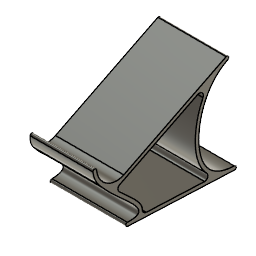
robot stand (Autodesk Fusion 360 design; units mm, degrees)
part number: 2026-07-23-08-51-04-627
Autodesk Fusion 360 part; units mm, degrees
sketch "Sketch1" plane through (0, 0, 0) normal (1, 0, 0) x (0, 1, 0)
  line L0 (-30, 0) -> (30, 30)
  arc A0 (-44.4721, 8.9443) -> (-30, 0) centre (-34.4721, 8.9443) ccw
  line L1 (30, -25) -> (-30, -25)
  arc A1 (-46.4721, 8.9443) -> (-43.4408, 0.9716) centre (-34.4721, 8.9443) ccw
  spline S0 degree 5 poles (-41.8278, -0.8884) (-40.6864, -2.2379) (-37.8165, -5.2912) (-32.5736, -10.0274) (-25.3421, -16.0716) (-21.7331, -20.6178) (-23.6292, -22.5666) (-27.4499, -23) (-30, -23) knots 0.240408 0.240408 0.240408 0.240408 0.240408 0.240408 0.4 0.6 0.8 1 1 1 1 1 1
  arc A2 (-44.4721, 8.9443) -> (-46.4721, 8.9443) centre (-45.4721, 8.9443) ccw
  arc A3 (-41.8278, -0.8884) -> (-43.4408, 0.9716) centre (-118.1793, -65.4675) ccw
  arc A4 (-30, -23) -> (-30, -25) centre (-30, -24) ccw
  spline S1 degree 5 poles (30.8944, 28.2111) (28.2124, 26.8701) (23.3204, 23.6383) (17.3979, 17.1432) (12.1889, 5.9253) (10.4091, -8.9335) (13.8806, -18.2883) (20.2615, -22.1429) (26.4338, -23) (30, -23) knots 0 0 0 0 0 0 0.2 0.4 0.6 0.8 1 1 1 1 1 1
  arc A5 (30, -25) -> (30, -23) centre (30, -24) ccw
  arc A6 (30.8944, 28.2111) -> (30, 30) centre (30.4472, 29.1056) ccw
  line L2 (-32.6162, -3.5442) -> (13.2688, 19.3983)
  line L3 (13.29, -23) -> (-19.3824, -23)
  spline S2 degree 3 poles (-33.0643, -6.8155) (-31.8146, -7.9472) (-30.5565, -9.0641) (-29.352, -10.1504) (-27.5469, -11.7781) (-25.8667, -13.332) (-24.5084, -14.8006) (-23.4896, -15.902) (-22.646, -16.9412) (-22.0594, -18.0481) (-21.6569, -18.8075) (-21.3515, -19.6249) (-21.3625, -20.5761) (-21.3634, -20.6591) (-21.3676, -20.743) (-21.3749, -20.8273) knots 0.416763 0.416763 0.416763 0.416763 0.500155 0.500155 0.500155 0.625116 0.625116 0.625116 0.718837 0.718837 0.718837 0.783141 0.783141 0.783141 0.788753 0.788753 0.788753 0.788753
  arc A7 (-32.6162, -3.5442) -> (-33.0643, -6.8155) centre (-31.7218, -5.333) ccw
  arc A8 (-21.3749, -20.8273) -> (-19.3824, -23) centre (-19.3824, -21) ccw
  arc A9 (15.883, 16.5885) -> (13.2688, 19.3983) centre (14.1632, 17.6095) ccw
  spline S3 degree 3 poles (15.883, 16.5885) (13.4429, 12.4786) (11.7105, 7.9169) (10.7147, 3.3266) (9.6034, -1.7957) (9.3986, -6.9504) (10.507, -11.5238) (11.2467, -14.5761) (12.6103, -17.3862) (14.7383, -19.6207) knots 0.254596 0.254596 0.254596 0.254596 0.439752 0.439752 0.439752 0.646367 0.646367 0.646367 0.784264 0.784264 0.784264 0.784264
  arc A10 (13.29, -23) -> (14.7383, -19.6207) centre (13.29, -21) ccw
  constraint concentric A0 A1
  constraint tangent L2 A9
  constraint tangent S3 A10
  constraint tangent L3 A10
extrude "Extrude1" add sketch "Sketch1" along normal mid plane 50
ref_plane "WorkPlane1" through (0, 0, 15) normal (0, -0.447214, 0.894427) x (0, -0.894427, -0.447214)
ref_plane "WorkPlane2" through (23.5767, 32.6206, 31.3103) normal (0, 0.894427, 0.447214) x (0, -0.447214, 0.894427)
sketch "Sketch5" plane through (0, 38.6206, 19.3103) normal (0, 0.894427, 0.447214) x (0, -0.447214, 0.894427)
  line L0 (13.4164, 0) -> (-11.5836, 0)
  line L1 (30.3358, 18.2803) -> (-45.6158, 26)
  line L2 (-45.6158, 26) -> (30.3358, 26)
  line L3 (30.3358, 26) -> (30.3358, 18.2803)
  line L4 (-45.6158, -26) -> (30.3358, -26)
  line L5 (30.3358, -26) -> (30.3358, -18.2803)
  line L6 (30.3358, -18.2803) -> (-45.6158, -26)
  constraint symmetric L0 L2.end L4.end
  constraint symmetric L0 L1.start L5.end
  constraint symmetric L0 L1.end L4.start
extrude "Extrude4" cut sketch "Sketch5" against normal blind 135
